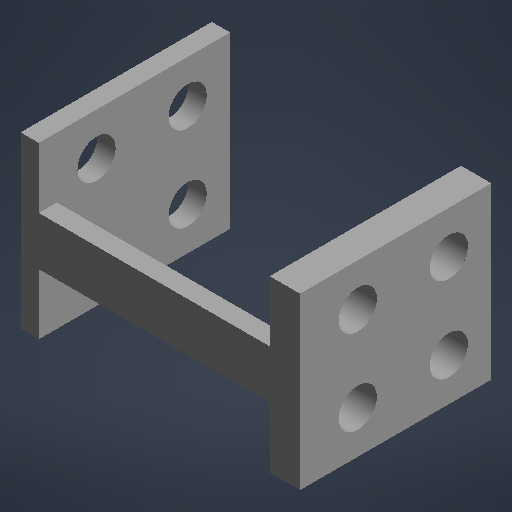
# Autodesk Inventor part: R2_rodilla_der
Saved by Autodesk Inventor 2027 (Build 310192060, 192F)
## iProperties
Part Number: R2_rodilla_der
Material: Genérico
Document SubType Name: Modelado
Designer: rodri
Appearance: Por defecto
Author: rodri
Autodesk Inventor part; units mm, degrees
ref_plane "Plano de trabajo1" through (0, 0, -14.5) normal (0, 0, 1) x (1, 0, 0)
sketch "Boceto1" plane through (0, 0, -14.5) normal (0, 0, 1) x (1, 0, 0)
  line L0 (-12.4, -99) -> (-7.4, -99)
  line L1 (-7.4, -99) -> (-7.4, -71)
  line L2 (-7.4, -71) -> (-12.4, -71)
  line L3 (-12.4, -71) -> (-12.4, -99)
  constraints: 8 end point, 2 parallel, 1 horizontal, 1 perpendicular
extrude "Extrusión1" add sketch "Boceto1" along normal blind 31.5
ref_plane "Plano de trabajo2" through (-12.5, 0, 0) normal (1, 0, 0) x (0, 1, 0)
sketch "Boceto2" plane through (-12.5, 0, 0) normal (1, 0, 0) x (0, 1, 0)
  circle A0 centre (-78, -7.5) radius 3.15
  constraints: 1 centre point
extrude "Extrusión2" cut sketch "Boceto2" along normal blind 5.2
ref_plane "Plano de trabajo3" through (-12.5, 0, 0) normal (1, 0, 0) x (0, 1, 0)
sketch "Boceto3" plane through (-12.5, 0, 0) normal (1, 0, 0) x (0, 1, 0)
  circle A0 centre (-78, 7.5) radius 3.15
  constraints: 1 centre point
extrude "Extrusión3" cut sketch "Boceto3" along normal blind 5.2
ref_plane "Plano de trabajo4" through (-12.5, 0, 0) normal (1, 0, 0) x (0, 1, 0)
sketch "Boceto4" plane through (-12.5, 0, 0) normal (1, 0, 0) x (0, 1, 0)
  circle A0 centre (-92, -7.5) radius 3.15
  constraints: 1 centre point
extrude "Extrusión4" cut sketch "Boceto4" along normal blind 5.2
ref_plane "Plano de trabajo5" through (-12.5, 0, 0) normal (1, 0, 0) x (0, 1, 0)
sketch "Boceto5" plane through (-12.5, 0, 0) normal (1, 0, 0) x (0, 1, 0)
  circle A0 centre (-92, 7.5) radius 3.15
  constraints: 1 centre point
extrude "Extrusión5" cut sketch "Boceto5" along normal blind 5.2
ref_plane "Plano de trabajo6" through (0, 0, -14.5) normal (0, 0, 1) x (1, 0, 0)
sketch "Boceto6" plane through (0, 0, -14.5) normal (0, 0, 1) x (1, 0, 0)
  line L0 (-53.4, -99) -> (-50.4, -99)
  line L1 (-50.4, -99) -> (-50.4, -71)
  line L2 (-50.4, -71) -> (-53.4, -71)
  line L3 (-53.4, -71) -> (-53.4, -99)
  constraints: 8 end point, 2 parallel, 1 horizontal, 1 perpendicular
extrude "Extrusión6" add sketch "Boceto6" along normal blind 31.5
ref_plane "Plano de trabajo7" through (-53.5, 0, 0) normal (1, 0, 0) x (0, 1, 0)
sketch "Boceto7" plane through (-53.5, 0, 0) normal (1, 0, 0) x (0, 1, 0)
  circle A0 centre (-78, -7.5) radius 3.15
  constraints: 1 centre point
extrude "Extrusión7" cut sketch "Boceto7" along normal blind 3.2
ref_plane "Plano de trabajo8" through (-53.5, 0, 0) normal (1, 0, 0) x (0, 1, 0)
sketch "Boceto8" plane through (-53.5, 0, 0) normal (1, 0, 0) x (0, 1, 0)
  circle A0 centre (-78, 7.5) radius 3.15
  constraints: 1 centre point
extrude "Extrusión8" cut sketch "Boceto8" along normal blind 3.2
ref_plane "Plano de trabajo9" through (-53.5, 0, 0) normal (1, 0, 0) x (0, 1, 0)
sketch "Boceto9" plane through (-53.5, 0, 0) normal (1, 0, 0) x (0, 1, 0)
  circle A0 centre (-92, -7.5) radius 3.15
  constraints: 1 centre point
extrude "Extrusión9" cut sketch "Boceto9" along normal blind 3.2
ref_plane "Plano de trabajo10" through (-53.5, 0, 0) normal (1, 0, 0) x (0, 1, 0)
sketch "Boceto10" plane through (-53.5, 0, 0) normal (1, 0, 0) x (0, 1, 0)
  circle A0 centre (-92, 7.5) radius 3.15
  constraints: 1 centre point
extrude "Extrusión10" cut sketch "Boceto10" along normal blind 3.2
ref_plane "Plano de trabajo11" through (0, 0, 14) normal (0, 0, 1) x (1, 0, 0)
sketch "Boceto11" plane through (0, 0, 14) normal (0, 0, 1) x (1, 0, 0)
  line L0 (-53.4, -89) -> (-7.4, -89)
  line L1 (-7.4, -89) -> (-7.4, -81)
  line L2 (-7.4, -81) -> (-53.4, -81)
  line L3 (-53.4, -81) -> (-53.4, -89)
  constraints: 8 end point, 2 parallel, 1 horizontal, 1 perpendicular
extrude "Extrusión11" add sketch "Boceto11" along normal blind 3
